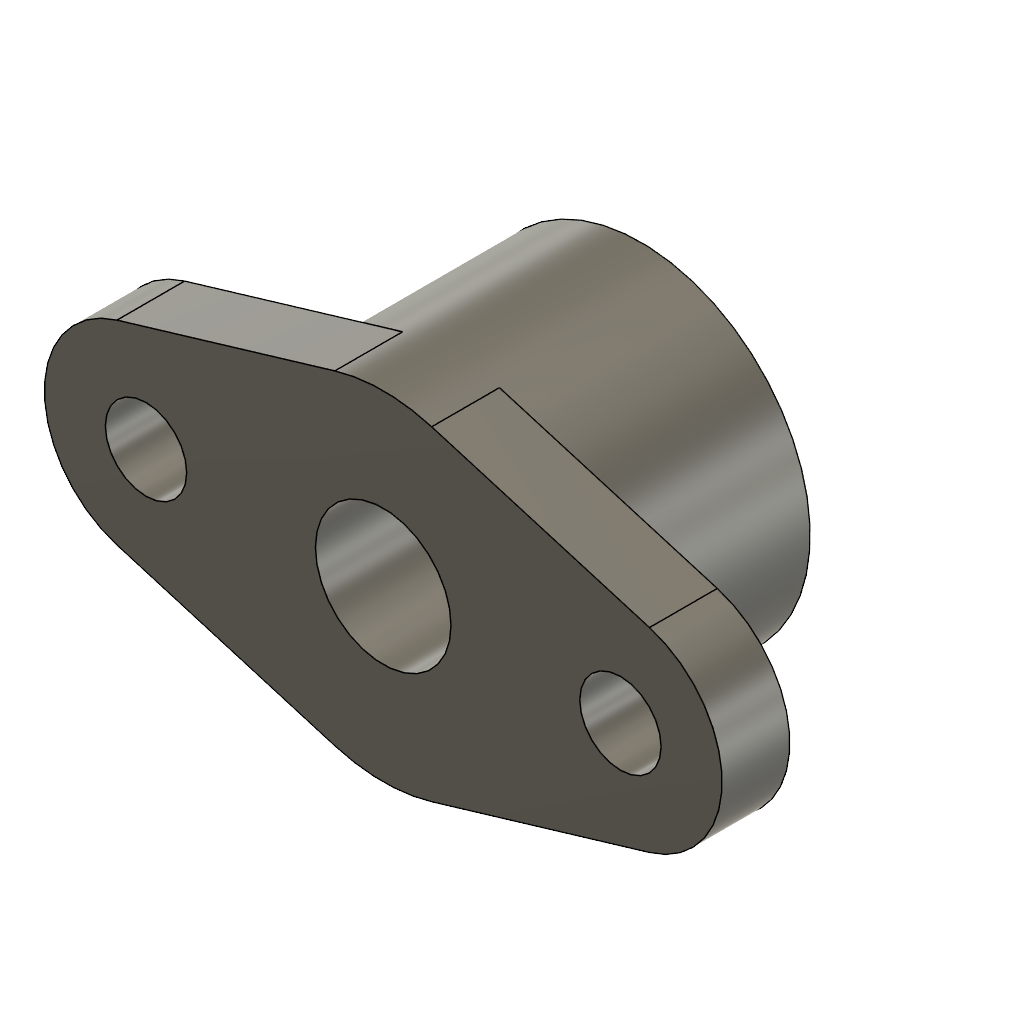
26015028 exercise 4.1(nithish R) (Autodesk Fusion 360 design; units mm, degrees)
part number: 2026-10-10-09-45-18-482
Autodesk Fusion 360 part; units mm, degrees
sketch "Sketch1" plane through (0, 0, 0) normal (0, 0, 1) x (1, 0, 0)
  circle A0 centre (-35, 0) radius 6
  line L0 (-39.2857, 14.3747) -> (-7.1429, 23.9579)
  line L1 (-39.2857, -14.3747) -> (0, -26.0875)
  circle A1 centre (35, 0) radius 6
  line L2 (39.2857, 14.3747) -> (7.1429, 23.9579)
  line L3 (39.2857, -14.3747) -> (0, -26.0875)
  arc A2 (-39.2857, 14.3747) -> (-39.2857, -14.3747) centre (-35, 0) ccw
  arc A3 (7.1429, 23.9579) -> (-7.1429, 23.9579) centre (0, 0) ccw
  arc A4 (-7.1429, -23.9579) -> (7.1429, -23.9579) centre (0, 0) ccw
  arc A5 (39.2857, -14.3747) -> (39.2857, 14.3747) centre (35, 0) ccw
  dimension "d1" = 50
  dimension "d2" = 12
  dimension "d3" = 30
  dimension "d4" = 35
  constraint coincident A3.centre A4.centre
  constraint concentric A0 A2
  constraint tangent L0 A3
  constraint tangent L0 A2
  constraint tangent L1 A4
  constraint tangent L1 A2
  constraint coincident L1 A4.start
  constraint coincident L3 A4.end
  measures "d1" diameter of A4
  measures "d2" diameter of A0
  measures "d3" diameter of A2
  measures "d4" distance of A3.centre A0.centre
extrude "Extrude1" add sketch "Sketch1" along normal blind 10 contours L0 L1 L2 L3 A2 A3 A4 A5
sketch "Sketch2" plane through (0, 0, 0) normal (0, 0, -1) x (-1, 0, 0)
  circle A0 centre (35, 0) radius 6
  circle A1 centre (-35, 0) radius 6
  arc A2 (39.2857, -14.3747) -> (39.2857, 14.3747) centre (35, 0) ccw
  line L0 (39.2857, 14.3747) -> (7.1429, 23.9579)
  arc A3 (7.1429, 23.9579) -> (-7.1429, 23.9579) centre (0, 0) ccw
  line L1 (-7.1429, 23.9579) -> (-39.2857, 14.3747)
  arc A4 (-39.2857, 14.3747) -> (-39.2857, -14.3747) centre (-35, 0) ccw
  line L2 (-39.2857, -14.3747) -> (-7.1429, -23.9579)
  arc A5 (-7.1429, -23.9579) -> (7.1429, -23.9579) centre (0, 0) ccw
  line L3 (7.1429, -23.9579) -> (39.2857, -14.3747)
  circle A6 centre (0, 0) radius 25
  dimension "d7" = 50
  constraint coincident A3.centre A5.centre
  measures "d7" diameter of A6
extrude "Extrude2" add sketch "Sketch2" along normal blind 28 contours A3 A5 A6
sketch "Sketch3" plane through (0, 0, -28) normal (0, 0, -1) x (-1, 0, 0)
  circle A0 centre (0, 0) radius 25
  circle A1 centre (0, 0) radius 10
  dimension "d10" = 20
  constraint concentric A0 A1
  measures "d10" diameter of A1
extrude "Extrude3" cut sketch "Sketch3" against normal blind 40 contours A1
sketch "Sketch4" plane through (0, 0, -28) normal (0, 0, -1) x (-1, 0, 0)
  circle A0 centre (0, 0) radius 10
  circle A1 centre (0, 0) radius 25
  circle A2 centre (0, 0) radius 15
  dimension "d13" = 30
  constraint coincident A0.centre A1.centre
  measures "d13" diameter of A2
sketch "Sketch5" plane through (0, 0, -28) normal (0, 0, -1) x (-1, 0, 0)
extrude "Extrude4" cut sketch "Sketch4" against normal blind 4 contours A2
sketch "Sketch6" plane through (0, 0, 0) normal (1, 0, 0) x (0, 0, -1)
  circle A0 centre (16, 0) radius 2
  point P0 (28, 0)
  dimension "d16" = 4
  dimension "d17" = 12
  measures "d16" diameter of A0
  measures "d17" distance of A0.centre P0
sketch "Sketch7" plane through (0, 0, 0) normal (0, 0, 1) x (1, 0, 0)
extrude "Extrude5" cut sketch "Sketch6" against normal blind 80
